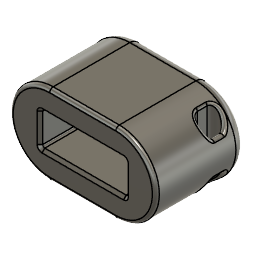
KeyModPlus_Cover (Autodesk Fusion 360 design; units mm, degrees)
Autodesk Fusion 360 part; units mm, degrees
sketch "草图1" plane through (0, 0, 0) normal (0, 0, 1) x (1, 0, 0)
  line L0 (-4.75, -5.75) -> (4.75, -5.75)
  arc A0 (4.75, -5.75) -> (4.75, 5.75) centre (4.75, 0) ccw
  line L1 (4.75, 5.75) -> (-4.75, 5.75)
  arc A1 (-4.75, 5.75) -> (-4.75, -5.75) centre (-4.75, 0) ccw
  line L2 (-4.75, 0) -> (4.75, 0) construction
  dimension "d1" = 11.5
  dimension "d44" = 9.5
  constraint tangent L0 A0
  constraint tangent A0 L1
  constraint parallel L0 L1
  constraint tangent L1 A1
  constraint tangent L0 A1
  constraint horizontal L2
  constraint midpoint L2 origin
  measures "d1" distance of L0 L1
  measures "d44" distance of A1.centre A0.centre
extrude "拉伸1" add sketch "草图1" along normal blind 13
sketch "草图2" plane through (0, 0, 13) normal (0, 0, 1) x (1, 0, 0)
  arc A0 (-4.75, 5.75) -> (-4.75, -5.75) centre (-4.75, 0) ccw
  line L0 (-4.75, -5.75) -> (4.75, -5.75)
  arc A1 (4.75, -5.75) -> (4.75, 5.75) centre (4.75, 0) ccw
  line L1 (4.75, 5.75) -> (-4.75, 5.75)
  line L2 (6.15, -2.375) -> (-6.15, -2.375)
  line L3 (-6.15, -2.375) -> (-6.15, 2.375)
  line L4 (-6.15, 2.375) -> (6.15, 2.375)
  line L5 (6.15, 2.375) -> (6.15, -2.375)
  line L6 (6.15, -2.375) -> (-6.15, 2.375) construction
  line L7 (-6.15, -2.375) -> (6.15, 2.375) construction
  dimension "d7" = 4.75
  dimension "d8" = 12.3
  constraint horizontal L2
  constraint perpendicular L2 L3
  constraint parallel L2 L4
  constraint parallel L3 L5
  constraint coincident L6 origin
  constraint coincident L7 origin
  measures "d7" distance of L2.start L4.end
  measures "d8" distance of L2.start L2.end
extrude "拉伸2" cut sketch "草图2" against normal blind 12 contours L2 L3 L4 L5
sketch "草图3" plane through (0, 2.375, 0) normal (0, -1, 0) x (1, 0, 0)
  line L0 (6.15, 13) -> (-6.15, 13)
  line L1 (-6.15, 13) -> (-6.15, 1)
  line L2 (-6.15, 1) -> (6.15, 1)
  line L3 (6.15, 1) -> (6.15, 13)
  line L4 (0, 1) -> (0, 13) construction
  line L5 (-1.75, 6.3) -> (-3.25, 6.3)
  line L6 (-3.25, 6.3) -> (-3.25, 7.7)
  line L7 (-3.25, 7.7) -> (-1.75, 7.7)
  line L8 (-1.75, 7.7) -> (-1.75, 6.3)
  line L9 (-1.75, 6.3) -> (-3.25, 7.7) construction
  line L10 (-3.25, 6.3) -> (-1.75, 7.7) construction
  line L11 (-4.75, 0) -> (-10.5, 0)
  line L12 (-4.75, 0) -> (4.75, 0)
  line L13 (10.5, 0) -> (4.75, 0)
  line L14 (4.75, 0) -> (-4.75, 0)
  line L15 (3.25, 7.7) -> (1.75, 7.7)
  line L16 (1.75, 6.3) -> (3.25, 6.3)
  line L17 (3.25, 6.3) -> (1.75, 7.7) construction
  line L18 (1.75, 6.3) -> (3.25, 7.7) construction
  line L19 (3.25, 6.3) -> (3.25, 7.7)
  line L20 (1.75, 7.7) -> (1.75, 6.3)
  point P0 (-2.5, 7)
  point P1 (2.5, 7)
  dimension "d11" = 6
  dimension "d12" = 1.4
  dimension "d13" = 1.5
  dimension "d14" = 2.5
  constraint midpoint L2 L4.start
  constraint midpoint L0 L4.end
  constraint horizontal L5
  constraint perpendicular L5 L6
  constraint parallel L5 L7
  constraint parallel L6 L8
  constraint coincident L9 P0
  constraint coincident L10 P0
  constraint symmetric L4 L5.start L16.start
  constraint symmetric L4 L5.end L16.end
  constraint symmetric L4 L6.end L15.start
  constraint symmetric L4 L7.end L15.end
  constraint symmetric L4 P0 P1
  measures "d11" distance of L0 P0
  measures "d12" distance of L5.start L7.end
  measures "d13" distance of L6.end L7.end
  measures "d14" distance of L4 P0
extrude "拉伸3" add sketch "草图3" along normal blind 0.2 contours L5 L6 L7 L8 | L15 L16 L19 L20
sketch "草图4" plane through (0, -2.375, 0) normal (0, 1, 0) x (-1, 0, 0)
  line L0 (6.15, 13) -> (-6.15, 13)
  line L1 (-6.15, 13) -> (-6.15, 1)
  line L2 (-6.15, 1) -> (6.15, 1)
  line L3 (6.15, 1) -> (6.15, 13)
  line L4 (0, 1) -> (0, 13) construction
  line L5 (-1.75, 6.3) -> (-3.25, 6.3)
  line L6 (-3.25, 6.3) -> (-3.25, 7.7)
  line L7 (-3.25, 7.7) -> (-1.75, 7.7)
  line L8 (-1.75, 7.7) -> (-1.75, 6.3)
  line L9 (-1.75, 6.3) -> (-3.25, 7.7) construction
  line L10 (-3.25, 6.3) -> (-1.75, 7.7) construction
  line L11 (1.75, 6.3) -> (3.25, 6.3)
  line L12 (3.25, 7.7) -> (1.75, 7.7)
  line L13 (1.75, 7.7) -> (1.75, 6.3)
  line L14 (3.25, 6.3) -> (1.75, 7.7) construction
  line L15 (3.25, 6.3) -> (3.25, 7.7)
  line L16 (1.75, 6.3) -> (3.25, 7.7) construction
  point P0 (-2.5, 7)
  point P1 (2.5, 7)
  dimension "d17" = 1.5
  dimension "d18" = 1.4
  dimension "d19" = 6
  dimension "d20" = 2.5
  constraint midpoint L2 L4.start
  constraint midpoint L0 L4.end
  constraint horizontal L5
  constraint perpendicular L5 L6
  constraint parallel L5 L7
  constraint parallel L6 L8
  constraint coincident L9 P0
  constraint coincident L10 P0
  constraint symmetric L4 L5.start L11.start
  constraint symmetric L4 L5.end L11.end
  constraint symmetric L4 L6.end L12.start
  constraint symmetric L4 L7.end L12.end
  constraint symmetric L4 P0 P1
  measures "d17" distance of L5.start L5.end
  measures "d18" distance of L5.start L7.end
  measures "d19" distance of L0 P0
  measures "d20" distance of L4 P0
extrude "拉伸4" add sketch "草图4" along normal blind 0.2 contours L5 L6 L7 L8 | L11 L12 L13 L15
fillet "圆角1" radius 0.2 16 edges at (1.75, 2.275, 7.7) (3.25, 2.275, 7.7) (3.25, 2.275, 6.3) (1.75, 2.275, 6.3) (-1.75, 2.275, 7.7) (-3.25, 2.275, 7.7) (-1.75, 2.275, 6.3) (-3.25, 2.275, 6.3) (-1.75, -2.275, 7.7) (-3.25, -2.275, 7.7) (-1.75, -2.275, 6.3) (-3.25, -2.275, 6.3) (1.75, -2.275, 7.7) (1.75, -2.275, 6.3) (3.25, -2.275, 7.7) (3.25, -2.275, 6.3)
fillet "圆角2" radius 0.2 32 edges at (3.1914, -2.175, 7.6414) (2.5, -2.175, 7.7) (1.8086, -2.175, 7.6414) (1.75, -2.175, 7) (1.8086, -2.175, 6.3586) (2.5, -2.175, 6.3) (3.1914, -2.175, 6.3586) (3.25, -2.175, 7) (-1.8086, -2.175, 7.6414) (-2.5, -2.175, 7.7) (-3.1914, -2.175, 7.6414) (-3.25, -2.175, 7) (-3.1914, -2.175, 6.3586) (-2.5, -2.175, 6.3) (-1.8086, -2.175, 6.3586) (-1.75, -2.175, 7) (-3.1914, 2.175, 7.6414) (-2.5, 2.175, 7.7) (-1.8086, 2.175, 7.6414) (-1.75, 2.175, 7) (-1.8086, 2.175, 6.3586) (-2.5, 2.175, 6.3) (-3.1914, 2.175, 6.3586) (-3.25, 2.175, 7) (1.8086, 2.175, 7.6414) (2.5, 2.175, 7.7) (3.1914, 2.175, 7.6414) (3.25, 2.175, 7) (3.1914, 2.175, 6.3586) (2.5, 2.175, 6.3) (1.8086, 2.175, 6.3586) (1.75, 2.175, 7)
fillet "圆角3" radius 1.5 4 edges at (-10.5, 0, 0) (0, -5.75, 0) (10.5, 0, 0) (0, 5.75, 0)
fillet "圆角4" radius 0.3 4 edges at (-6.15, 2.375, 7) (-6.15, -2.375, 7) (6.15, -2.375, 7) (6.15, 2.375, 7)
chamfer "倒角1" distance 0.4 angle 45 8 edges at (0, -2.375, 13) (-6.0621, -2.2871, 13) (-6.15, 0, 13) (-6.0621, 2.2871, 13) (0, 2.375, 13) (6.0621, 2.2871, 13) (6.15, 0, 13) (6.0621, -2.2871, 13)
fillet "圆角6" radius 0.5 4 edges at (10.5, 0, 13) (0, 5.75, 13) (-10.5, 0, 13) (0, -5.75, 13)
sketch "草图5" plane through (0, 5.75, 0) normal (0, 1, 0) x (-1, 0, 0)
  line L0 (4.75, 12.5) -> (-4.75, 12.5)
  line L1 (-4.75, 12.5) -> (-4.75, 1.5)
  line L2 (-4.75, 1.5) -> (4.75, 1.5)
  line L3 (4.75, 1.5) -> (4.75, 12.5)
  line L4 (-9.35, 4.2) -> (-9.35, 2.8)
  arc A0 (-9.35, 2.8) -> (-7.65, 2.8) centre (-8.5, 2.8) ccw
  line L5 (-7.65, 2.8) -> (-7.65, 4.2)
  arc A1 (-7.65, 4.2) -> (-9.35, 4.2) centre (-8.5, 4.2) ccw
  line L6 (-8.5, 4.2) -> (-8.5, 2.8) construction
  point P0 (-8.5, 3.5)
  dimension "d36" = 1.7
  dimension "d37" = 1.4
  dimension "d38" = 3.5
  dimension "d39" = 8.5
  constraint tangent L4 A0
  constraint tangent A0 L5
  constraint parallel L4 L5
  constraint tangent L5 A1
  constraint tangent L4 A1
  constraint vertical L6
  constraint midpoint L6 P0
  measures "d36" distance of L4 L5
  measures "d37" distance of A1.centre A0.centre
  measures "d38" vertical distance of origin P0
  measures "d39" horizontal distance of origin P0
extrude "拉伸5" cut sketch "草图5" against normal blind 13 contours L4 A0 L5 A1
fillet "圆角7" radius 0.4 8 edges at (8.5552, -4.3108, 1.9518) (7.65, -4.9651, 3.5) (8.5552, -4.3108, 5.0482) (9.35, -3.45, 3.5) (8.5552, 4.3108, 1.9518) (9.35, 3.45, 3.5) (8.5552, 4.3108, 5.0482) (7.65, 4.9651, 3.5)
named bodies: "KeyModPlus-Cover"
